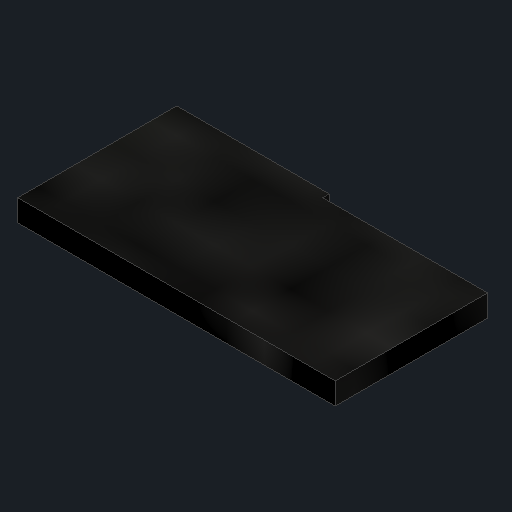
# Autodesk Inventor part: usb_cable_compact
Saved by Autodesk Inventor 2027.1 (Build 311270010, 270A)
## iProperties
Created: 2026-10-29
Part Number: usb_cable_compact
Material: Generic
Document SubType Name: Modeling
Designer: alexg
Density: 1 g/cm^3
Appearance: Smooth - Black
Author: alexg
Autodesk Inventor part; units mm, degrees
ref_plane "YZ Plane" through (0, 0, 0) normal (1, 0, 0) x (0, 1, 0)
ref_plane "Work Plane1" through (0, -26.34, 0) normal (0, 1, 0) x (-1, 0, 0)
sketch "Run along Pi edge sketch" plane through (0, -26.34, 0) normal (0, 1, 0) x (-1, 0, 0)
  line L0 (27.5, -12.5) -> (12.93, -12.5)
  line L1 (12.93, -12.5) -> (12.93, -5.5)
  line L2 (12.93, -5.5) -> (27.5, -5.5)
  line L3 (27.5, -5.5) -> (27.5, -12.5)
  constraints: 8 end point, 2 parallel, 1 horizontal, 1 perpendicular
extrude "Run along Pi edge" add sketch "Run along Pi edge sketch" along normal blind 1
ref_plane "Work Plane2" through (0, -26.34, 0) normal (0, 1, 0) x (-1, 0, 0)
sketch "Fold into socket sketch" plane through (0, -26.34, 0) normal (0, 1, 0) x (-1, 0, 0)
  line L0 (27.5, -12.8) -> (20.5, -12.8)
  line L1 (20.5, -12.8) -> (20.5, -12.5)
  line L2 (20.5, -12.5) -> (27.5, -12.5)
  line L3 (27.5, -12.5) -> (27.5, -12.8)
  constraints: 8 end point, 2 parallel, 1 horizontal, 1 perpendicular
extrude "Fold into socket" add sketch "Fold into socket sketch" along normal blind 1
body "Solid1"
